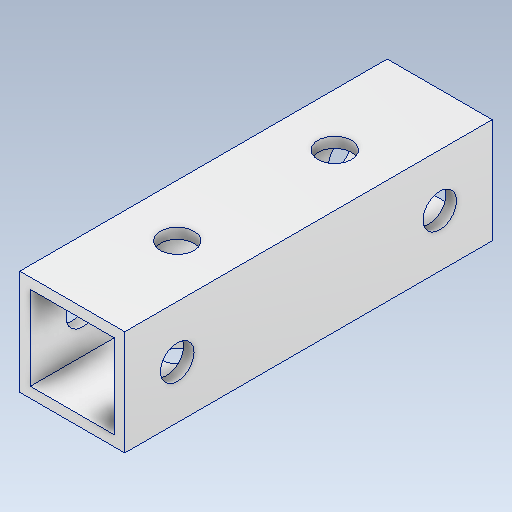
# Autodesk Inventor part: alsp_10_10_35_1
Saved by Autodesk Inventor 2027.1 (Build 311270010, 270A)
## iProperties
Created: 2026-10-20
Part Number: alsp_10_10_35_1
Material: アルミニウム 6061
Document SubType Name: Modeling
Designer: ug_nd
Density: 2.7 g/cm^3
Appearance: アルミニウム - フラット
Author: ug_nd
Autodesk Inventor part; units mm, degrees
ref_plane "YZ Plane" through (0, 0, 0) normal (1, 0, 0) x (0, 1, 0)
ref_plane "XZ Plane" through (0, 0, 0) normal (0, 1, 0) x (-1, 0, 0)
ref_plane "XY Plane" through (0, 0, 0) normal (0, 0, 1) x (1, 0, 0)
sketch "スケッチ1" plane through (0, 0, 0) normal (0, 0, 1) x (1, 0, 0)
  line L0 (-5, -5) -> (5, -5)
  line L1 (5, -5) -> (5, 5)
  line L2 (5, 5) -> (-5, 5)
  line L3 (-5, 5) -> (-5, -5)
  line L4 (-5, -5) -> (5, 5) construction
  line L5 (5, -5) -> (-5, 5) construction
  line L6 (-4, -4) -> (4, -4)
  line L7 (4, -4) -> (4, 4)
  line L8 (4, 4) -> (-4, 4)
  line L9 (-4, 4) -> (-4, -4)
  line L10 (-4, -4) -> (4, 4) construction
  line L11 (4, -4) -> (-4, 4) construction
  point P0 (0, 0)
  dimension "d0" = 10
  dimension "d1" = 10
  dimension "d2" = 1
  dimension "d3" = 1
  constraints: 24 end point, 4 midpoint, 4 parallel, 2 horizontal, 2 perpendicular
  measures "d0" distance of L1.end L2.end
  measures "d1" distance of L2.end L0.start
  measures "d2" distance between parallel lines of L3 L9
  measures "d3" distance between parallel lines of L8 L2
extrude "押し出し1" add sketch "スケッチ1" along normal mid plane 35
sketch "スケッチ2" plane through (-5, 5, 17.5) normal (0, 1, 0) x (1, 0, 0)
  line L0 (-2, 17.5) -> (12, 17.5) construction
  line L1 (5, 42) -> (5, -7) construction
  circle A0 centre (5, 25) radius 1.6
  circle A1 centre (5, 10) radius 1.6
  point P0 (5, 17.5)
  dimension "d6" = 15
  dimension "d7" = 3.2
  constraints: 2 centre point, 1 point on line, 1 symmetric about line, 1 other
  measures "d6" distance of A0.centre A1.centre
  measures "d7" diameter of A0
extrude "押し出し2" cut sketch "スケッチ2" against normal through all
sketch "スケッチ3" plane through (5, -5, 17.5) normal (1, 0, 0) x (0, 0, -1)
  line L0 (17.5, -2) -> (17.5, 12) construction
  line L1 (42, 5) -> (-7, 5) construction
  circle A0 centre (5, 5) radius 1.6
  circle A1 centre (30, 5) radius 1.6
  point P0 (17.5, 5)
  dimension "d10" = 25
  dimension "d11" = 3.2
  constraints: 2 centre point, 1 point on line, 1 symmetric about line, 1 other
  measures "d10" distance of A1.centre A0.centre
  measures "d11" diameter of A1
extrude "押し出し3" cut sketch "スケッチ3" against normal through all
